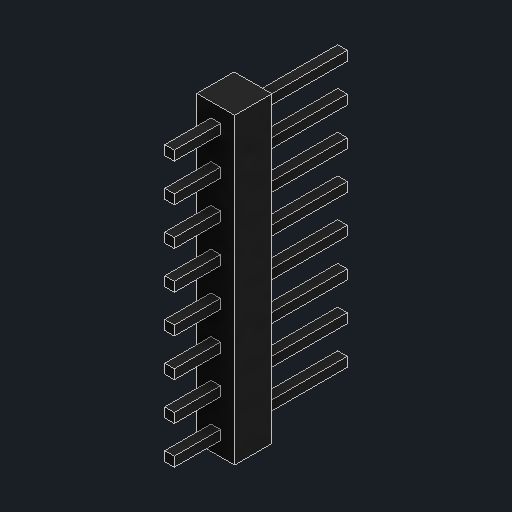
# Autodesk Inventor part: tft_1.8in_header_1x8
Saved by Autodesk Inventor 2027.1 (Build 311270010, 270A)
## iProperties
Created: 2026-10-29
Part Number: tft_1.8in_header_1x8
Material: Generic
Document SubType Name: Modeling
Designer: alexg
Density: 1 g/cm^3
Appearance: Black
Author: alexg
Autodesk Inventor part; units mm, degrees
ref_plane "YZ Plane" through (0, 0, 0) normal (1, 0, 0) x (0, 1, 0)
ref_plane "Work Plane1" through (0, 0, 23.8) normal (0, 0, 1) x (1, 0, 0)
sketch "Header plastic 1x8 sketch" plane through (0, 0, 23.8) normal (0, 0, 1) x (1, 0, 0)
  line L0 (22.31, 32.34) -> (24.85, 32.34)
  line L1 (24.85, 32.34) -> (24.85, 52.66)
  line L2 (24.85, 52.66) -> (22.31, 52.66)
  line L3 (22.31, 52.66) -> (22.31, 32.34)
  constraints: 8 end point, 2 parallel, 1 horizontal, 1 perpendicular
extrude "Header plastic 1x8" add sketch "Header plastic 1x8 sketch" against normal blind 2.5
ref_plane "Work Plane2" through (0, 0, 26.9) normal (0, 0, 1) x (1, 0, 0)
sketch "Header pins sketch" plane through (0, 0, 26.9) normal (0, 0, 1) x (1, 0, 0)
  line L0 (23.26, 33.29) -> (23.9, 33.29)
  line L1 (23.9, 33.29) -> (23.9, 33.93)
  line L2 (23.9, 33.93) -> (23.26, 33.93)
  line L3 (23.26, 33.93) -> (23.26, 33.29)
  line L4 (23.26, 35.83) -> (23.9, 35.83)
  line L5 (23.9, 35.83) -> (23.9, 36.47)
  line L6 (23.9, 36.47) -> (23.26, 36.47)
  line L7 (23.26, 36.47) -> (23.26, 35.83)
  line L8 (23.26, 38.37) -> (23.9, 38.37)
  line L9 (23.9, 38.37) -> (23.9, 39.01)
  line L10 (23.9, 39.01) -> (23.26, 39.01)
  line L11 (23.26, 39.01) -> (23.26, 38.37)
  line L12 (23.26, 40.91) -> (23.9, 40.91)
  line L13 (23.9, 40.91) -> (23.9, 41.55)
  line L14 (23.9, 41.55) -> (23.26, 41.55)
  line L15 (23.26, 41.55) -> (23.26, 40.91)
  line L16 (23.26, 43.45) -> (23.9, 43.45)
  line L17 (23.9, 43.45) -> (23.9, 44.09)
  line L18 (23.9, 44.09) -> (23.26, 44.09)
  line L19 (23.26, 44.09) -> (23.26, 43.45)
  line L20 (23.26, 45.99) -> (23.9, 45.99)
  line L21 (23.9, 45.99) -> (23.9, 46.63)
  line L22 (23.9, 46.63) -> (23.26, 46.63)
  line L23 (23.26, 46.63) -> (23.26, 45.99)
  line L24 (23.26, 48.53) -> (23.9, 48.53)
  line L25 (23.9, 48.53) -> (23.9, 49.17)
  line L26 (23.9, 49.17) -> (23.26, 49.17)
  line L27 (23.26, 49.17) -> (23.26, 48.53)
  line L28 (23.26, 51.07) -> (23.9, 51.07)
  line L29 (23.9, 51.07) -> (23.9, 51.71)
  line L30 (23.9, 51.71) -> (23.26, 51.71)
  line L31 (23.26, 51.71) -> (23.26, 51.07)
  constraints: 64 end point, 16 parallel, 8 horizontal, 8 perpendicular
extrude "Header pins" add sketch "Header pins sketch" against normal blind 11.6
body "Solid1"
